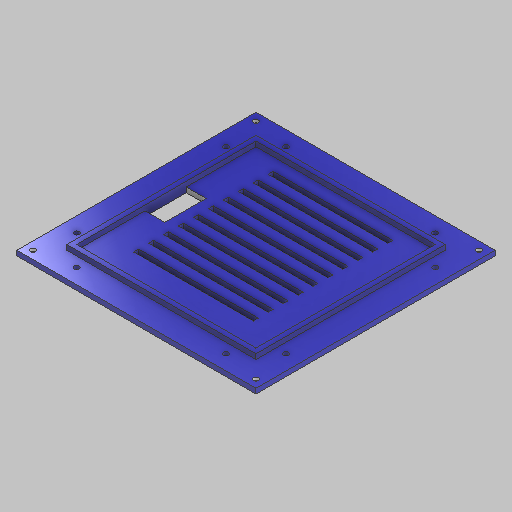
# Autodesk Inventor part: Carcasa_inferior
Saved by Autodesk Inventor 2027 (Build 310192000, 192)
## iProperties
Created: 2026-11-23
Part Number: Carcasa_inferior
Material: Genérico
Document SubType Name: Modeling
Designer: Alexander
Density: 1 g/cm^3
Appearance: Valor por defecto
Author: Alexander
Autodesk Inventor part; units mm, degrees
ref_plane "YZ Plane" through (0, 0, 0) normal (1, 0, 0) x (0, 1, 0)
ref_plane "XZ Plane" through (0, 0, 0) normal (0, 1, 0) x (-1, 0, 0)
ref_plane "XY Plane" through (0, 0, 0) normal (0, 0, 1) x (1, 0, 0)
sketch "Boceto1" plane through (0, 0, 0) normal (0, 1, 0) x (-1, 0, 0)
  line L0 (95, 95) -> (-95, 95)
  line L1 (-95, 95) -> (-95, -95)
  line L2 (-95, -95) -> (95, -95)
  line L3 (95, -95) -> (95, 95)
  line L4 (90, 90) -> (-90, 90)
  line L5 (-90, 90) -> (-90, -90)
  line L6 (-90, -90) -> (90, -90)
  line L7 (90, -90) -> (90, 90)
  line L8 (120, 120) -> (-120, 120)
  line L9 (-120, 120) -> (-120, -120)
  line L10 (-120, -120) -> (120, -120)
  line L11 (120, -120) -> (120, 120)
  circle A0 centre (-105, 75) radius 2.5
  circle A1 centre (-105, -75) radius 2.5
  circle A2 centre (75, 105) radius 2.5
  circle A3 centre (-75, 105) radius 2.5
  circle A4 centre (105, 75) radius 2.5
  circle A5 centre (105, -75) radius 2.5
  circle A6 centre (75, -105) radius 2.5
  circle A7 centre (-75, -105) radius 2.5
  point P0 (0, 0)
  point P1 (-90, 0)
  point P2 (0, 90)
  point P3 (0, -95)
  point P4 (95, 0)
  dimension "d0" = 95
  dimension "d1" = 190
  dimension "d2" = 190
  dimension "d3" = 95
  dimension "d4" = 5
  dimension "d5" = 5
  dimension "d6" = 5
  dimension "d7" = 5
  dimension "d8" = 240
  dimension "d9" = 240
  dimension "d10" = 120
  dimension "d11" = 120
  dimension "d12" = 5
  dimension "d13" = 5
  dimension "d14" = 5
  dimension "d15" = 5
  dimension "d16" = 5
  dimension "d17" = 5
  dimension "d18" = 5
  dimension "d19" = 5
  dimension "d20" = 150
  dimension "d21" = 150
  dimension "d23" = 150
  dimension "d24" = 150
  dimension "d25" = 75
  dimension "d26" = 75
  dimension "d27" = 75
  dimension "d28" = 75
  dimension "d29" = 10
  dimension "d30" = 10
  dimension "d31" = 10
  dimension "d32" = 10
  dimension "d33" = 10
  dimension "d34" = 10
  constraints: 24 end point, 8 centre point, 6 parallel, 4 midpoint, 3 horizontal, 3 perpendicular
  measures "d0" distance from line of point (0, 0) L2
  measures "d1" distance of L2.end L0.start
  measures "d2" distance of L1.end L2.end
  measures "d3" distance from line of L3 point (0, 0)
  measures "d4" distance between parallel lines of L3 L7
  measures "d5" distance between parallel lines of L4 L0
  measures "d6" distance between parallel lines of L5 L1
  measures "d7" distance between parallel lines of L6 L2
  measures "d8" distance of L10.end L8.start
  measures "d9" distance of L9.end L10.end
  measures "d10" distance from line of point (0, 0) L10
  measures "d11" distance from line of point (0, 0) L11
  measures "d12" diameter of A0
  measures "d13" diameter of A1
  measures "d14" diameter of A2
  measures "d15" diameter of A3
  measures "d16" diameter of A4
  measures "d17" diameter of A5
  measures "d18" diameter of A6
  measures "d19" diameter of A7
  measures "d20" distance of A1.centre A0.centre
  measures "d21" distance of A6.centre A7.centre
  measures "d23" distance of A5.centre A4.centre
  measures "d24" distance of A3.centre A2.centre
  measures "d25" vertical distance of A0.centre point (-90, 0)
  measures "d26" horizontal distance of A3.centre point (0, 90)
  measures "d27" horizontal distance of A7.centre point (0, -95)
  measures "d28" vertical distance of A5.centre point (95, 0)
  measures "d29" distance from line of L0 A2.centre
  measures "d30" distance from line of L0 A3.centre
  measures "d31" distance from line of A0.centre L1
  measures "d32" distance from line of A6.centre L2
  measures "d33" distance from line of A7.centre L2
  measures "d34" distance from line of A5.centre L3
extrude "Extrusión1" add sketch "Boceto1" against normal blind 5 contours L3 L2 L1 L0 | L7 L6 L5 L4 | L11 L10 L9 L8 | A0 | A1 | A2 | A3 | A4 | A5 | A6 | A7
extrude "Extrusión2" add sketch "Boceto1" along normal blind 5 contours L3 L2 L1 L0
extrude "Extrusión3" cut sketch "Boceto1" against normal blind 5 contours A0 | A1 | A2 | A3 | A4 | A5 | A6 | A7
sketch "Boceto2" plane through (0, 0, 0) normal (0, 1, 0) x (1, 0, 0)
  line L0 (-60, 77.187) -> (60, 77.187)
  line L1 (60, 77.187) -> (60, 72.187)
  line L2 (60, 72.187) -> (-60, 72.187)
  line L3 (-60, 72.187) -> (-60, 77.187)
  line L4 (90, 90) -> (90, -90) projected
  line L5 (-60, 62.187) -> (60, 62.187)
  line L6 (60, 62.187) -> (60, 57.187)
  line L7 (60, 57.187) -> (-60, 57.187)
  line L8 (-60, 57.187) -> (-60, 62.187)
  line L9 (-60, 47.187) -> (60, 47.187)
  line L10 (60, 47.187) -> (60, 42.187)
  line L11 (60, 42.187) -> (-60, 42.187)
  line L12 (-60, 42.187) -> (-60, 47.187)
  line L13 (-60, 32.187) -> (60, 32.187)
  line L14 (60, 32.187) -> (60, 27.187)
  line L15 (60, 27.187) -> (-60, 27.187)
  line L16 (-60, 27.187) -> (-60, 32.187)
  line L17 (-60, 17.187) -> (60, 17.187)
  line L18 (60, 17.187) -> (60, 12.187)
  line L19 (60, 12.187) -> (-60, 12.187)
  line L20 (-60, 12.187) -> (-60, 17.187)
  line L21 (-60, 2.187) -> (60, 2.187)
  line L22 (60, 2.187) -> (60, -2.813)
  line L23 (60, -2.813) -> (-60, -2.813)
  line L24 (-60, -2.813) -> (-60, 2.187)
  line L25 (-60, -12.813) -> (60, -12.813)
  line L26 (60, -12.813) -> (60, -17.813)
  line L27 (60, -17.813) -> (-60, -17.813)
  line L28 (-60, -17.813) -> (-60, -12.813)
  line L29 (-60, -27.813) -> (60, -27.813)
  line L30 (60, -27.813) -> (60, -32.813)
  line L31 (60, -32.813) -> (-60, -32.813)
  line L32 (-60, -32.813) -> (-60, -27.813)
  line L33 (-60, -42.813) -> (60, -42.813)
  line L34 (60, -42.813) -> (60, -47.813)
  line L35 (60, -47.813) -> (-60, -47.813)
  line L36 (-60, -47.813) -> (-60, -42.813)
  line L37 (-60, -57.813) -> (60, -57.813)
  line L38 (60, -57.813) -> (60, -62.813)
  line L39 (60, -62.813) -> (-60, -62.813)
  line L40 (-60, -62.813) -> (-60, -57.813)
  point P0 (0, 0)
  dimension "d41" = 120
  dimension "d42" = 5
  dimension "d43" = 30
  dimension "d46" = 15
  constraints: 80 end point, 2 parallel, 1 collinear, 1 horizontal, 1 perpendicular, 1 vertical, 71 other
  measures "d41" distance of L1.end L2.end
  measures "d42" distance of L0.end L1.end
  measures "d43" distance between parallel lines of L4 L1
  measures "d46" distance of L0.start L5.start
extrude "Extrusión4" cut sketch "Boceto2" against normal blind 5
sketch "Boceto3" plane through (0, 0, 0) normal (0, 1, 0) x (1, 0, 0)
  line L0 (120, 120) -> (-120, 120) projected
  line L1 (-120, 120) -> (-120, -120) projected
  line L2 (-120, -120) -> (120, -120) projected
  line L3 (120, -120) -> (120, 120) projected
  circle A0 centre (112, 112) radius 2.5
  circle A1 centre (-112, 112) radius 2.5
  circle A2 centre (-112, -112) radius 2.5
  circle A3 centre (112, -112) radius 2.5
  point P0 (0, 0)
  dimension "d58" = 8
  dimension "d59" = 8
  dimension "d60" = 8
  dimension "d61" = 8
  dimension "d62" = 8
  dimension "d63" = 8
  dimension "d64" = 8
  dimension "d65" = 8
  dimension "d66" = 5
  dimension "d67" = 5
  dimension "d68" = 5
  dimension "d69" = 5
  constraints: 4 centre point, 4 coincident
  measures "d58" distance from line of point (-112, 112) L0
  measures "d59" distance from line of L1 point (-112, 112)
  measures "d60" distance from line of L2 point (-112, -112)
  measures "d61" distance from line of L1 point (-112, -112)
  measures "d62" distance from line of L2 point (112, -112)
  measures "d63" distance from line of L3 point (112, -112)
  measures "d64" distance from line of point (112, 112) L0
  measures "d65" distance from line of L3 point (112, 112)
  measures "d66" diameter of A0
  measures "d67" diameter of A1
  measures "d68" diameter of A2
  measures "d69" diameter of A3
extrude "Extrusión5" cut sketch "Boceto3" against normal blind 5 contours A0 | A1 | A2 | A3
sketch "Boceto4" plane through (0, 0, 0) normal (0, 1, 0) x (1, 0, 0)
  circle A0 centre (-112, 112) radius 2.5 projected
  circle A1 centre (-112, 112) radius 2.5
  circle A2 centre (112, 112) radius 2.5 projected
  circle A3 centre (112, 112) radius 2.5
  circle A4 centre (-112, -112) radius 2.5 projected
  circle A5 centre (-112, -112) radius 2.5
  circle A6 centre (112, -112) radius 2.5 projected
  circle A7 centre (112, -112) radius 2.5
  line L0 (-120, 120) -> (-120, -120) projected
  line L1 (120, 120) -> (120, -120) projected
  line L2 (-120, 120) -> (120, 120)
  line L3 (120, 120) -> (120, -120)
  line L4 (120, -120) -> (-120, -120)
  line L5 (-120, -120) -> (-120, 120)
  line L6 (-115, 0) -> (-110, 0)
  line L7 (-110, 0) -> (-110, 60)
  line L8 (-110, 60) -> (-115, 60)
  line L9 (-115, 60) -> (-115, 0)
  line L10 (-115, 0) -> (-110, 0)
  line L11 (-110, 0) -> (-110, -60)
  line L12 (-110, -60) -> (-115, -60)
  line L13 (-115, -60) -> (-115, 0)
  line L14 (110, 60) -> (115, 60)
  line L15 (115, 60) -> (115, 0)
  line L16 (115, 0) -> (110, 0)
  line L17 (110, 0) -> (110, 60)
  line L18 (110, 0) -> (115, 0)
  line L19 (115, 0) -> (115, -60)
  line L20 (115, -60) -> (110, -60)
  line L21 (110, -60) -> (110, 0)
  line L22 (0, -115) -> (-60, -115)
  line L23 (-60, -115) -> (-60, -110)
  line L24 (-60, -110) -> (0, -110)
  line L25 (0, -110) -> (0, -115)
  line L26 (0, -115) -> (60, -115)
  line L27 (60, -115) -> (60, -110)
  line L28 (60, -110) -> (0, -110)
  line L29 (0, -110) -> (0, -115)
  line L30 (0, 110) -> (-60, 110)
  line L31 (-60, 110) -> (-60, 115)
  line L32 (-60, 115) -> (0, 115)
  line L33 (0, 115) -> (0, 110)
  line L34 (0, 110) -> (60, 110)
  line L35 (60, 110) -> (60, 115)
  line L36 (60, 115) -> (0, 115)
  line L37 (0, 115) -> (0, 110)
  point P0 (0, 0)
  point P1 (112.5, 0)
  dimension "d72" = 5
  dimension "d73" = 60
  dimension "d74" = 5
  dimension "d75" = 60
  dimension "d76" = 5
  dimension "d77" = 60
  dimension "d78" = 5
  dimension "d79" = 60
  dimension "d80" = 60
  dimension "d81" = 5
  dimension "d82" = 60
  dimension "d83" = 5
  dimension "d84" = 60
  dimension "d85" = 5
  constraints: 72 end point, 18 parallel, 9 horizontal, 9 perpendicular, 4 centre point, 4 coincident, 3 point on line, 1 midpoint
  measures "d72" distance of L8.end L7.end
  measures "d73" distance of L7.end L6.end
  measures "d74" distance between parallel lines of L0 L9
  measures "d75" distance of L10.end L11.end
  measures "d76" distance between parallel lines of L15 L1
  measures "d77" distance from line of point (112.5, 0) L14
  measures "d78" distance between parallel lines of L15 L17
  measures "d79" distance of L18.end L19.end
  measures "d80" distance of L23.end L24.end
  measures "d81" distance of L22.end L23.end
  measures "d82" distance of L28.end L27.end
  measures "d83" distance between parallel lines of L4 L26
  measures "d84" distance of L36.end L35.end
  measures "d85" distance between parallel lines of L2 L32
sketch "Boceto5" plane through (0, -5, 0) normal (0, -1, 0) x (1, 0, 0)
  line L0 (97.5, 97.5) -> (-97.5, 97.5)
  line L1 (-97.5, 97.5) -> (-97.5, -97.5)
  line L2 (-97.5, -97.5) -> (97.5, -97.5)
  line L3 (97.5, -97.5) -> (97.5, 97.5)
  circle A0 centre (97.5, 97.5) radius 10
  circle A1 centre (97.5, -97.5) radius 10
  circle A2 centre (-97.5, 97.5) radius 10
  circle A3 centre (-97.5, -97.5) radius 10
  circle A4 centre (97.5, 97.5) radius 7.5
  circle A5 centre (97.5, -97.5) radius 7.5
  circle A6 centre (-97.5, 97.5) radius 7.5
  circle A7 centre (-97.5, -97.5) radius 7.5
  point P0 (0, 0)
  dimension "d86" = 195
  dimension "d87" = 195
  dimension "d88" = 97.5
  dimension "d89" = 97.5
  dimension "d90" = 20
  dimension "d91" = 20
  dimension "d92" = 20
  dimension "d93" = 20
  dimension "d94" = 15
  dimension "d95" = 15
  dimension "d96" = 15
  dimension "d97" = 15
  constraints: 8 centre point, 8 coincident, 8 end point, 2 parallel, 1 horizontal, 1 perpendicular
  measures "d86" distance of L2.end L1.end
  measures "d87" distance of L1.end L0.end
  measures "d88" distance from line of point (0, 0) L0
  measures "d89" distance from line of L1 point (0, 0)
  measures "d90" diameter of A0
  measures "d91" diameter of A1
  measures "d92" diameter of A2
  measures "d93" diameter of A3
  measures "d94" diameter of A4
  measures "d95" diameter of A5
  measures "d96" diameter of A6
  measures "d97" diameter of A7
extrude "Extrusión6" add sketch "Boceto5" along normal blind 10 contours A2 L1 A6 L0 | L0 A6 L1 A2 | A0 L3 A4 L0 | L0 A4 L3 A0 | A3 L2 A7 L1 | L1 A7 L2 A3 | A1 L2 A5 L3 | L3 A5 L2 A1
sketch "Boceto6" plane through (0, -5, 0) normal (0, -1, 0) x (1, 0, 0)
  circle A0 centre (112, 112) radius 2.5 projected
  circle A1 centre (112, 112) radius 5
  circle A2 centre (112, -112) radius 2.5 projected
  circle A3 centre (112, -112) radius 5
  circle A4 centre (-112, -112) radius 2.5 projected
  circle A5 centre (-112, -112) radius 5
  circle A6 centre (-112, 112) radius 2.5 projected
  circle A7 centre (-112, 112) radius 5
  point P0 (0, 0)
  dimension "d100" = 10
  dimension "d101" = 10
  dimension "d102" = 10
  dimension "d103" = 10
  constraints: 4 centre point, 4 coincident
  measures "d100" diameter of A1
  measures "d101" diameter of A3
  measures "d102" diameter of A5
  measures "d103" diameter of A7
extrude "Extrusión7" cut sketch "Boceto6" against normal blind 2
sketch "Boceto7" plane through (0, 0, 0) normal (0, 1, 0) x (1, 0, 0)
  line L0 (-90, -90) -> (-90, 90) projected
  line L1 (-90, 0) -> (-70, 0)
  line L2 (-70, 0) -> (-70, 20)
  line L3 (-70, 20) -> (-90, 20)
  line L4 (-90, 20) -> (-90, 0)
  line L5 (-70, 0) -> (-90, 0)
  line L6 (-90, 0) -> (-90, -21.5176)
  line L7 (-90, -21.5176) -> (-70, -21.5176)
  line L8 (-70, -21.5176) -> (-70, 0)
  point P0 (0, 0)
  dimension "d106" = 20
  dimension "d107" = 20
  dimension "d108" = 20
  constraints: 16 end point, 4 parallel, 2 horizontal, 2 perpendicular, 1 midpoint
  measures "d106" distance of L3.end L2.end
  measures "d107" distance of L2.end L1.end
  measures "d108" distance of L7.end L6.end
extrude "Extrusión8" cut sketch "Boceto7" against normal blind 23
equation "\"d0\" = 0.5 * d1"
equation "\"d3\" = 0.5 * d2"
equation "\"d10\" = 0.5 * d8"
equation "\"d11\" = 0.5 * d9"
equation "\"d25\" = 0.5 * d20"
equation "\"d26\" = 0.5 * d24"
equation "\"d27\" = 0.5 * d21"
equation "\"d28\" = 0.5 * d23"
equation "\"d88\" = 0.5 * d87"
equation "\"d89\" = 0.5 * d86"
